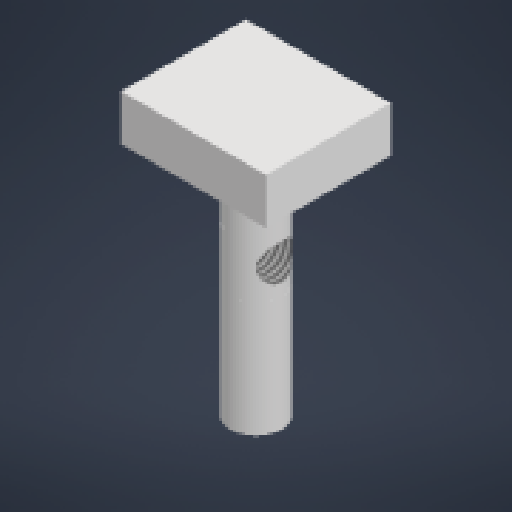
# Autodesk Inventor part: truc_khop_3
Saved by Autodesk Inventor 2026.2 (Build 302298000, 298)
## iProperties
Created: 2026-04-03
Part Number: truc_khop_3
Material: Generic
Document SubType Name: Modeling
Designer: thita
Density: 1 g/cm^3
Appearance: Default
Author: thita
Autodesk Inventor part; units mm, degrees
ref_plane "YZ Plane" through (0, 0, 0) normal (1, 0, 0) x (0, 1, 0)
ref_plane "XZ Plane" through (0, 0, 0) normal (0, 1, 0) x (-1, 0, 0)
ref_plane "XY Plane" through (0, 0, 0) normal (0, 0, 1) x (1, 0, 0)
sketch "Sketch1" plane through (0, 0, 0) normal (0, 1, 0) x (-1, 0, 0)
  circle A0 centre (0, 0) radius 2.8
  dimension "d0" = 5.6
  constraints: 1 centre point, 1 coincident
  measures "d0" diameter of A0
extrude "Extrusion1" add sketch "Sketch1" along normal blind 25
sketch "Sketch2" plane through (0, 0, 0) normal (0, -1, 0) x (1, 0, 0)
  circle A0 centre (0, 0) radius 2
  dimension "d3" = 4
  constraints: 1 centre point, 1 coincident
  measures "d3" diameter of A0
extrude "Extrusion2" cut sketch "Sketch2" against normal blind 3
sketch "Sketch3" plane through (0, 25, 0) normal (0, 1, 0) x (1, 0, 0)
  line L0 (7.9, -6.8) -> (7.9, 6.8)
  line L1 (7.9, 6.8) -> (-7.9, 6.8)
  line L2 (-7.9, 6.8) -> (-7.9, -6.8)
  line L3 (-7.9, -6.8) -> (7.9, -6.8)
  line L4 (7.9, -6.8) -> (-7.9, 6.8) construction
  line L5 (7.9, 6.8) -> (-7.9, -6.8) construction
  point P0 (0, 0)
  dimension "d6" = 13.6
  dimension "d7" = 15.8
  constraints: 12 end point, 2 midpoint, 2 parallel, 1 perpendicular, 1 vertical
  measures "d6" distance of L0.start L0.end
  measures "d7" distance of L1.end L0.end
extrude "Extrusion3" add sketch "Sketch3" along normal blind 5
sketch "Sketch6" plane through (0, 0, 0) normal (0, 0, 1) x (1, 0, 0)
  line L0 (2.8, 0) -> (-2.8, 0) projected
  line L1 (2.8, 0) -> (2.8, 25) projected
  line L2 (2.8, 12.5) -> (0, 12.5)
  line L3 (0, 12.5) -> (0, 18.5)
  line L4 (0, 18.5) -> (-2.8, 18.5)
  line L5 (-2.8, 0) -> (-2.8, 25) projected
  point P0 (0, 0)
  dimension "d19" = 6
  constraints: 6 end point, 2 perpendicular, 1 horizontal, 1 midpoint, 1 point on line
  measures "d19" distance of L2.end L3.end
split body "Split2" sketch "Sketch6" result two bodies curves L2 L3 L4 first body at (-0.4471, 10.3333, 2.2561)
sketch "Sketch7" plane through (0, 0, 0) normal (1, 0, 0) x (0, 1, 0)
  circle A0 centre (15.8203, 0) radius 2
  point P0 (0, 0)
  dimension "d20" = 4
  constraints: 1 centre point
  measures "d20" diameter of A0
extrude "Extrusion5" cut sketch "Sketch7" along normal mid plane 10 bodies 3 2
thread "Thread2" size "M4x0.7" class "6H" standard "ISO Metric profile" length 12
thread "Thread3" size "M4x0.7" class "6H" standard "ISO Metric profile" length 12
body "Solid4"
body "Solid5"
